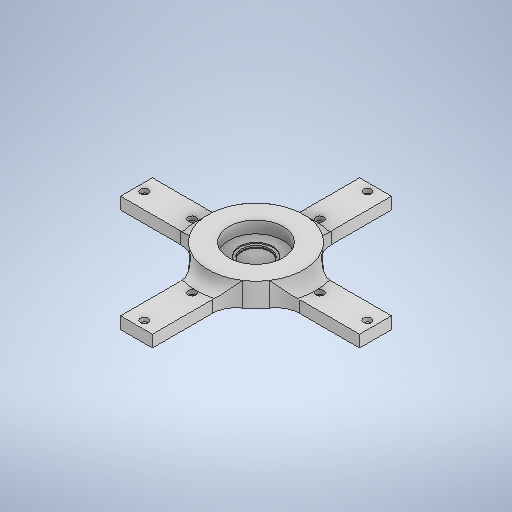
# Autodesk Inventor part: 底部支架1
Saved by Autodesk Inventor 2025 (Build 290162000, 162)
## iProperties
Created: 2026-11-18
Part Number: 底部支架1
Material: 常规
Document SubType Name: Modeling
Designer: ylh00
Density: 1 g/cm^3
Appearance: 默认
Author: ylh00
Autodesk Inventor part; units mm, degrees
ref_plane "YZ Plane" through (0, 0, 0) normal (1, 0, 0) x (0, 1, 0)
ref_plane "XZ Plane" through (0, 0, 0) normal (0, 1, 0) x (-1, 0, 0)
ref_plane "XY Plane" through (0, 0, 0) normal (0, 0, 1) x (1, 0, 0)
sketch "草图3" plane through (0, 0, 0) normal (0, 1, 0) x (-1, 0, 0)
  circle A0 centre (0, 0) radius 34.1
  circle A1 centre (0, 0) radius 60
  dimension "d2" = 68.2
  dimension "d3" = 120
  constraints: 2 centre point, 2 coincident
  measures "d2" diameter of A0
  measures "d3" diameter of A1
extrude "拉伸1" add sketch "草图3" along normal blind 15
sketch "草图4" plane through (0, 0, 0) normal (0, -1, 0) x (1, 0, 0)
  line L0 (-20, 175) -> (20, 175)
  line L1 (20, 175) -> (20, -175)
  line L2 (20, -175) -> (-20, -175)
  line L3 (-20, -175) -> (-20, 175)
  line L4 (-20, 175) -> (20, -175) construction
  line L5 (20, 175) -> (-20, -175) construction
  line L6 (-175, 20) -> (-175, -20)
  line L7 (-175, -20) -> (175, -20)
  line L8 (175, -20) -> (175, 20)
  line L9 (175, 20) -> (-175, 20)
  line L10 (-175, 20) -> (175, -20) construction
  line L11 (-175, -20) -> (175, 20) construction
  circle A0 centre (0, 0) radius 60
  point P0 (56.5685, 20)
  point P1 (20, 56.5685)
  point P2 (-20, 56.5685)
  point P3 (-56.5685, 20)
  point P4 (-56.5685, -20)
  point P5 (-20, -56.5685)
  point P6 (20, -56.5685)
  point P7 (56.5685, -20)
  dimension "d6" = 40
  dimension "d7" = 350
  dimension "d8" = 40
  dimension "d9" = 350
  constraints: 24 end point, 5 parallel, 4 midpoint, 2 perpendicular, 1 centre point, 1 coincident, 1 horizontal
  measures "d6" distance of L0.start L0.end
  measures "d7" distance of L0.end L1.end
  measures "d8" distance of L6.start L6.end
  measures "d9" distance of L7.end L6.end
extrude "拉伸2" add sketch "草图4" along normal blind 15
fillet "圆角1" radius 15 5 edges at (0, 0, -60) (-59.1359, 0, 10.1461) (-59.1359, 0, -10.1461) (0, 0, 60) (60, 0, 0)
fillet "圆角2" radius 30 14 edges at (-56.5685, -7.5, -20) (-56.5685, 7.5, -20) (-56.5685, 0, 20) (-20, -7.5, -56.5685) (-20, 7.5, -56.5685) (20, -7.5, -56.5685) (20, 7.5, -56.5685) (56.5685, -7.5, -20) (56.5685, 7.5, -20) (56.5685, -7.5, 20) (56.5685, 7.5, 20) (20, 7.5, 56.5685) (20, -7.5, 56.5685) (-20, 0, 56.5685)
sketch "草图5" plane through (0, 0, 0) normal (0, 1, 0) x (1, 0, 0)
  circle A0 centre (0, 0) radius 17.6
  dimension "d14" = 35.2
  constraints: 1 centre point, 1 coincident
  measures "d14" diameter of A0
extrude "拉伸3" cut sketch "草图5" against normal blind 4
sketch "草图6" plane through (0, 0, 0) normal (0, 1, 0) x (1, 0, 0)
  arc A0 (33.3333, 49.8888) -> (-33.3333, 49.8888) centre (0, 0) ccw projected
  circle A1 centre (0, 0) radius 18
  dimension "d17" = 36
  constraints: 1 centre point, 1 coincident
  measures "d17" diameter of A1
extrude "拉伸4" cut sketch "草图6" against normal blind 3
sketch "草图7" plane through (0, 0, 0) normal (0, 1, 0) x (1, 0, 0)
  circle A0 centre (0, 0) radius 21
  dimension "d20" = 42
  constraints: 1 centre point, 1 coincident
  measures "d20" diameter of A0
extrude "拉伸5" cut sketch "草图7" against normal blind 1.2
thicken "加厚1" operation cut thickness 25 both sides no extend neighbours no toward (0, 0, -1) faces at (6.6667, -10, 175)
thicken "加厚2" operation cut thickness 25 both sides no extend neighbours no toward (-1, 0, 0) faces at (175, -10, -6.6667)
thicken "加厚3" operation cut thickness 25 both sides no extend neighbours no toward (0, 0, 1) faces at (-6.6667, -10, -175)
thicken "加厚4" operation cut thickness 25 both sides no extend neighbours no toward (1, 0, 0) faces at (-175, -10, 6.6667)
sketch "草图10" plane through (0, 15, 0) normal (0, 1, 0) x (1, 0, 0)
  circle A0 centre (-80, 0) radius 2.5
  circle A1 centre (-140, 0) radius 2.5
  circle A2 centre (0, -80) radius 2.5
  circle A3 centre (0, -140) radius 2.5
  circle A4 centre (80, 0) radius 2.5
  circle A5 centre (140, 0) radius 2.5
  circle A6 centre (0, 80) radius 2.5
  circle A7 centre (0, 140) radius 2.5
  point P0 (0, 0)
  dimension "d53" = 5
  dimension "d54" = 5
  dimension "d57" = 360
  constraints: 8 centre point, 17 other
  measures "d53" diameter of A0
  measures "d54" diameter of A1
extrude "拉伸8" cut sketch "草图10" against normal blind 100
sketch "草图11" plane through (0, 0, 0) normal (0, 1, 0) x (1, 0, 0)
  circle A0 centre (-80, 0) radius 2.5 projected
  circle A1 centre (-80, 0) radius 5
  arc A2 (-72.2533, 20.1111) -> (-72.2533, -20.1111) centre (0, 0) ccw projected
  circle A3 centre (-140, 0) radius 2.5 projected
  circle A4 centre (-140, 0) radius 5
  circle A5 centre (0, -80) radius 5
  circle A6 centre (0, -140) radius 5
  circle A7 centre (80, 0) radius 5
  circle A8 centre (140, 0) radius 5
  circle A9 centre (0, 80) radius 5
  circle A10 centre (0, 140) radius 5
  dimension "d63" = 360
  constraints: 8 centre point, 2 coincident, 1 tangent, 17 other
extrude "拉伸9" cut sketch "草图11" against normal blind 5 contours A0 | A1 | A3 | A4 | A5 | A6 | A7 | A8 | A9 | A10
